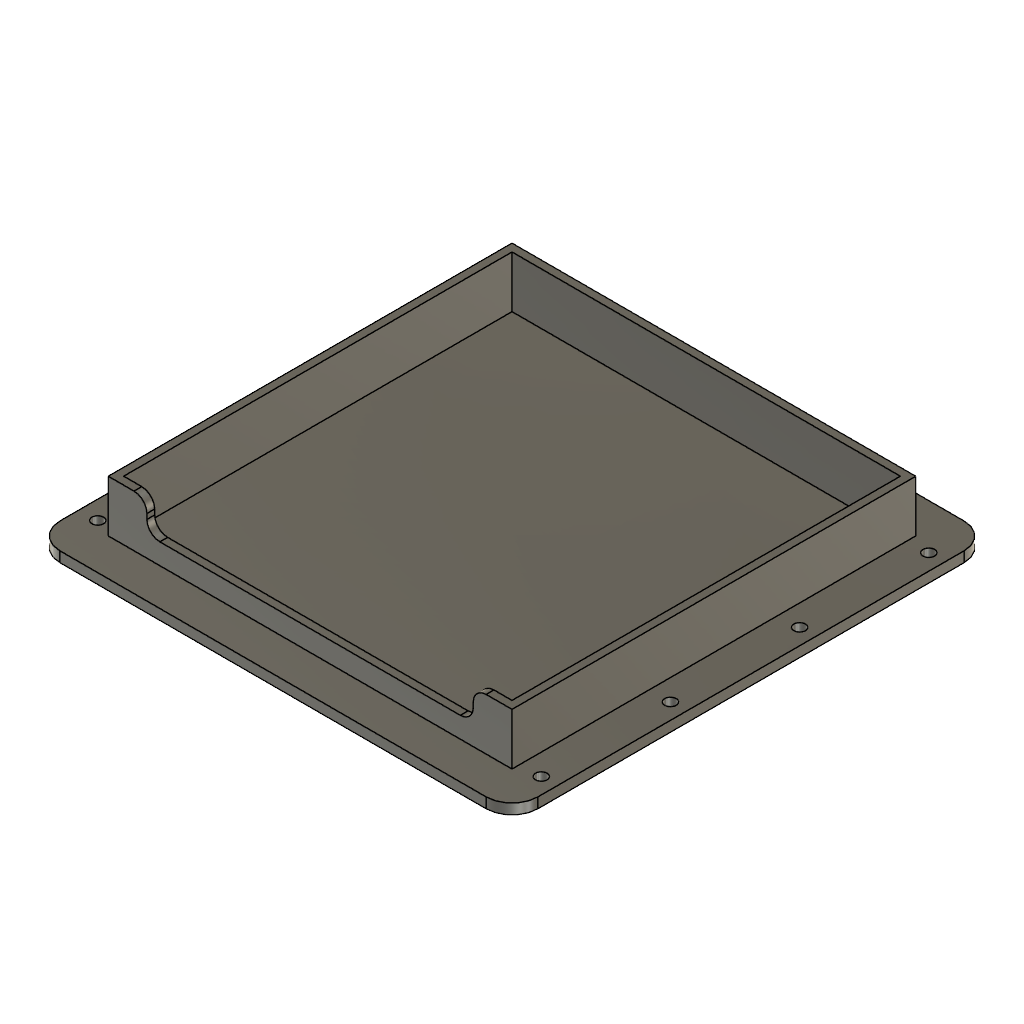
canasta (Autodesk Fusion 360 design; units mm, degrees)
Autodesk Fusion 360 part; units mm, degrees
sketch "Boceto1" plane through (0, 0, 0) normal (0, 0, 1) x (1, 0, 0)
  line L0 (92.5, 92.5) -> (-92.5, 92.5)
  line L1 (-92.5, 92.5) -> (-92.5, -92.5)
  line L2 (-92.5, -92.5) -> (92.5, -92.5)
  line L3 (92.5, -92.5) -> (92.5, 92.5)
  line L4 (92.5, 92.5) -> (-92.5, -92.5) construction
  line L5 (-92.5, 92.5) -> (92.5, -92.5) construction
  dimension "d1" = 185
  dimension "d2" = 185
  constraint horizontal L0
  constraint perpendicular L0 L1
  constraint parallel L0 L2
  constraint parallel L1 L3
  constraint coincident L4 origin
  constraint coincident L5 origin
  measures "d1" distance of L0.start L2.end
  measures "d2" distance of L1.end L2.end
extrude "Extruir1" add sketch "Boceto1" along normal blind 3
sketch "Boceto2" plane through (0, 0, 3) normal (0, 0, 1) x (-1, 0, 0)
  line L0 (-92.5, 92.5) -> (-92.5, -92.5)
  line L1 (-92.5, -92.5) -> (92.5, -92.5)
  line L2 (92.5, -92.5) -> (92.5, 92.5)
  line L3 (92.5, 92.5) -> (-92.5, 92.5)
  line L4 (-75.15, -75.15) -> (75.15, -75.15)
  line L5 (75.15, -75.15) -> (75.15, 75.15)
  line L6 (75.15, 75.15) -> (-75.15, 75.15)
  line L7 (-75.15, 75.15) -> (-75.15, -75.15)
  line L8 (-75.15, -75.15) -> (75.15, 75.15) construction
  line L9 (75.15, -75.15) -> (-75.15, 75.15) construction
  line L10 (78.15, 78.15) -> (-78.15, 78.15)
  line L11 (-78.15, 78.15) -> (-78.15, -78.15)
  line L12 (-78.15, -78.15) -> (78.15, -78.15)
  line L13 (78.15, -78.15) -> (78.15, 78.15)
  dimension "d6" = 150.3
  dimension "d7" = 150.3
  dimension "d8" = 3
  constraint horizontal L4
  constraint perpendicular L4 L5
  constraint parallel L4 L6
  constraint parallel L5 L7
  constraint coincident L8 origin
  constraint coincident L9 origin
  measures "d6" distance of L5.end L6.end
  measures "d7" distance of L4.end L5.end
extrude "Extruir2" add sketch "Boceto2" along normal blind 20 contours L10 L11 L12 L13
sketch "Boceto3" plane through (0, -78.15, 0) normal (0, -1, 0) x (1, 0, 0)
  line L0 (-78.15, 3) -> (78.15, 3)
  line L1 (78.15, 3) -> (78.15, 23)
  line L2 (78.15, 23) -> (-78.15, 23)
  line L3 (-78.15, 23) -> (-78.15, 3)
  line L4 (-63.15, 23) -> (63.15, 23)
  line L5 (63.15, 23) -> (63.15, 11)
  line L6 (63.15, 11) -> (-63.15, 11)
  line L7 (-63.15, 11) -> (-63.15, 23)
  line L8 (0, 23) -> (0, 15) construction
  dimension "d12" = 15
  dimension "d28" = 8
  constraint horizontal L4
  constraint vertical L5
  constraint horizontal L6
  constraint vertical L7
  constraint coincident L2 L4.start
  constraint midpoint L2 L8.start
  constraint perpendicular L2 L8
  constraint symmetric L5 L7 L8
  measures "d12" distance of L3 L7
  measures "d28" distance of L0 L6
extrude "Extruir3" cut sketch "Boceto3" against normal blind 3 contours L2 L4 L5 L6 L7
sketch "Boceto4" plane through (0, 0, 3) normal (0, 0, 1) x (-1, 0, 0)
  line L0 (-92.5, 92.5) -> (-92.5, -92.5)
  line L1 (-92.5, -92.5) -> (92.5, -92.5)
  line L2 (92.5, -92.5) -> (92.5, 92.5)
  line L3 (92.5, 92.5) -> (-92.5, 92.5)
  line L4 (-78.15, 78.15) -> (78.15, 78.15)
  line L5 (78.15, 78.15) -> (78.15, -78.15)
  line L6 (78.15, -78.15) -> (-78.15, -78.15)
  line L7 (-78.15, -78.15) -> (-78.15, 78.15)
  line L8 (92.5, 0) -> (78.15, 0) construction
  line L9 (85.325, 0) -> (85.325, -92.5) construction
  point P0 (85.325, -75)
  point P1 (-86.3249, -75)
  point P2 (-86.3249, -25)
  point P3 (85.325, -25)
  point P4 (85.325, 25)
  point P5 (-86.3249, 25)
  point P6 (85.325, 75)
  point P7 (-86.3249, 75)
  dimension "d16" = 50
  dimension "d17" = 50
  dimension "d18" = 50
  dimension "d31" = 25
  constraint horizontal P0 P1
  constraint vertical P1 P2
  constraint horizontal P2 P3
  constraint vertical P0 P3
  constraint horizontal P4 P5
  constraint horizontal P6 P7
  constraint vertical P3 P4
  constraint vertical P4 P6
  constraint vertical P2 P5
  constraint vertical P5 P7
  constraint midpoint L2 L8.start
  constraint midpoint L5 L8.end
  constraint midpoint L8 L9.start
  constraint coincident L1 L9.end
  constraint perpendicular L1 L9
  constraint coincident P0 L9
  measures "d16" distance of P0 P3
  measures "d17" distance of P3 P4
  measures "d18" distance of P4 P6
  measures "d31" distance of P3 L8
hole "Agujero1" at (86.3249, 75, 3) at (86.3249, 25, 3) at (86.3249, -25, 3) at (86.3249, -75, 3) at (-85.325, -75, 3) at (-85.325, -25, 3) at (-85.325, 25, 3) at (-85.325, 75, 3) direction (0, 0, -1) diameter 4.5 end through all
fillet "Empalme2" radius 10 4 edges at (92.5, -92.5, 1.5) (92.5, 92.5, 1.5) (-92.5, 92.5, 1.5) (-92.5, -92.5, 1.5)
extrude "Extruir4" add 1 faces at (28.3771, -58.1664, 0) along direction (0, 0, -1) blind 1
fillet "Empalme3" radius 5 4 edges at (-63.15, -76.65, 23) (-63.15, -76.65, 11) (63.15, -76.65, 11) (63.15, -76.65, 23)
equation "t = 0.3 mm"
equation "d6 = 150 mm + t"
equation "d7 = 150 mm + t"
